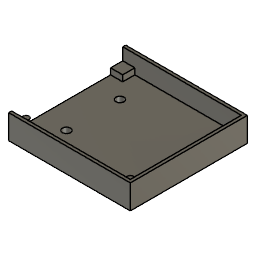
Controller Mounting (Autodesk Fusion 360 design; units mm, degrees)
Autodesk Fusion 360 part; units mm, degrees
sketch "Sketch1" plane through (0, 0, 0) normal (0, 0, 1) x (1, 0, 0)
  line L0 (0, 0) -> (65.175, 0)
  line L1 (65.175, 0) -> (65.175, 61.175)
  line L2 (65.175, 61.175) -> (0, 61.175)
  line L3 (0, 61.175) -> (0, 0)
  dimension "d1" = 61.175
  dimension "d2" = 65.175
  constraint horizontal L0
  constraint vertical L1
  constraint horizontal L2
  constraint vertical L3
  constraint coincident L0.start L3.end
  measures "d1" distance of L0.start L2.end
  measures "d2" distance of L0.start L0.end
extrude "Extrude1" add sketch "Sketch1" along normal blind 12.7
sketch "Sketch4" plane through (0, 0, 12.7) normal (0, 0, 1) x (-1, 0, 0)
  line L0 (0, -61.175) -> (0, 0)
  line L1 (0, 0) -> (-65.175, 0)
  line L2 (-65.175, 0) -> (-65.175, -61.175)
  line L3 (-65.175, -61.175) -> (0, -61.175)
  line L4 (-1.5875, -1.5875) -> (-63.5875, -1.5875)
  line L5 (-63.5875, -1.5875) -> (-63.5875, -59.5875)
  line L6 (-63.5875, -59.5875) -> (-1.5875, -59.5875)
  line L7 (-1.5875, -59.5875) -> (-1.5875, -1.5875)
  dimension "d10" = 1.5875
  dimension "d11" = 1.5875
  dimension "d12" = 1.5875
  dimension "d13" = 1.5875
  constraint horizontal L4
  constraint vertical L5
  constraint horizontal L6
  constraint vertical L7
  measures "d10" distance of L0 L7
  measures "d11" distance of L3 L6
  measures "d12" distance of L1 L4
  measures "d13" distance of L2 L5
extrude "Extrude2" cut sketch "Sketch4" against normal blind 9.525 contours L4 L5 L6 L7
sketch "Sketch5" plane through (0, 0, 0) normal (-1, 0, 0) x (0, -1, 0)
  line L0 (-61.175, 0) -> (0, 0)
  line L1 (0, 0) -> (0, 12.7)
  line L2 (0, 12.7) -> (-61.175, 12.7)
  line L3 (-61.175, 12.7) -> (-61.175, 0)
  line L4 (-53.2375, 12.7) -> (-7.9375, 12.7)
  line L5 (-7.9375, 12.7) -> (-7.9375, 0)
  line L6 (-53.2375, 0) -> (-53.2375, 12.7)
  line L7 (-53.2375, 3.175) -> (-59.5875, 3.175)
  line L8 (-59.5875, 3.175) -> (-59.5875, 12.7)
  line L9 (-59.5875, 12.7) -> (-53.2375, 12.7)
  line L10 (-53.2375, 12.7) -> (-53.2375, 3.175)
  line L11 (-7.9375, 3.175) -> (-1.5875, 3.175)
  line L12 (-1.5875, 3.175) -> (-1.5875, 12.7)
  line L13 (-1.5875, 12.7) -> (-7.9375, 12.7)
  line L14 (-7.9375, 12.7) -> (-7.9375, 3.175)
  line L15 (-53.2375, 3.175) -> (-7.9375, 3.175)
  dimension "d76" = 1.5875
  dimension "d77" = 3.175
  dimension "d78" = 3.175
  dimension "d79" = 1.5875
  dimension "d80" = 6.35
  dimension "d81" = 6.35
  constraint horizontal L4
  constraint vertical L5
  constraint vertical L6
  constraint coincident L2 L4.start
  constraint horizontal L5.end L6.start
  constraint horizontal L0.end L6.start
  constraint horizontal L7
  constraint vertical L8
  constraint horizontal L9
  constraint vertical L10
  constraint coincident L2 L8.end
  constraint coincident L6 L7.start
  constraint horizontal L11
  constraint vertical L12
  constraint horizontal L13
  constraint vertical L14
  constraint coincident L2 L12.end
  constraint coincident L5 L11.start
  measures "d76" distance of L3 L8
  measures "d77" distance of L0 L7
  measures "d78" distance of L0 L11
  measures "d79" distance of L1 L12
  measures "d80" distance of L8 L10
  measures "d81" distance of L12 L14
extrude "Extrude3" cut sketch "Sketch5" against normal blind 1.5875
sketch "Sketch6" plane through (0, 0, 3.175) normal (0, 0, 1) x (-1, 0, 0)
  circle A0 centre (-59.8375, -5.3375) radius 1.65
  circle A1 centre (-5.3375, -5.3375) radius 1.65
  circle A2 centre (-59.8375, -55.8375) radius 1.65
  circle A3 centre (-5.3375, -55.8375) radius 1.65
  line L0 (-63.5875, -1.5875) -> (-57.2375, -1.5875)
  line L1 (-57.2375, -1.5875) -> (-57.2375, -7.9375)
  line L2 (-57.2375, -7.9375) -> (-63.5875, -7.9375)
  line L3 (-63.5875, -7.9375) -> (-63.5875, -1.5875)
  line L4 (-63.5875, -59.5875) -> (-57.2375, -59.5875)
  line L5 (-57.2375, -59.5875) -> (-57.2375, -53.2375)
  line L6 (-57.2375, -53.2375) -> (-63.5875, -53.2375)
  line L7 (-63.5875, -53.2375) -> (-63.5875, -59.5875)
  line L8 (-1.5875, -59.5875) -> (-7.9375, -59.5875)
  line L9 (-7.9375, -59.5875) -> (-7.9375, -53.2375)
  line L10 (-7.9375, -53.2375) -> (-1.5875, -53.2375)
  line L11 (-1.5875, -53.2375) -> (-1.5875, -59.5875)
  line L12 (-1.5875, -1.5875) -> (-7.9375, -1.5875)
  line L13 (-7.9375, -1.5875) -> (-7.9375, -7.9375)
  line L14 (-7.9375, -7.9375) -> (-1.5875, -7.9375)
  line L15 (-1.5875, -7.9375) -> (-1.5875, -1.5875)
  line L16 (-65.175, 0) -> (-65.175, -61.175)
  line L17 (-65.175, -61.175) -> (0, -61.175)
  line L18 (-1.5875, -1.5875) -> (-63.5875, -1.5875)
  line L19 (-63.5875, -1.5875) -> (-63.5875, -59.5875)
  line L20 (-63.5875, -59.5875) -> (-1.5875, -59.5875)
  line L21 (-1.5875, -59.5875) -> (-1.5875, -1.5875)
  dimension "d82" = 3.3
  dimension "d83" = 50.5
  dimension "d84" = 50.5
  dimension "d85" = 54.5
  dimension "d86" = 3.3
  dimension "d87" = 3.3
  dimension "d88" = 5.3375
  dimension "d89" = 5.3375
  dimension "d90" = 6.35
  dimension "d91" = 6.35
  dimension "d92" = 6.35
  dimension "d93" = 6.35
  dimension "d94" = 6.35
  dimension "d95" = 6.35
  dimension "d96" = 6.35
  dimension "d97" = 6.35
  dimension "d98" = 1.5875
  dimension "d100" = 1.5875
  dimension "d101" = 1.5875
  dimension "d102" = 1.5875
  constraint horizontal A0.centre A1.centre
  constraint horizontal A2.centre A3.centre
  constraint vertical A1.centre A3.centre
  constraint equal A0 A1
  constraint horizontal L0
  constraint vertical L1
  constraint horizontal L2
  constraint vertical L3
  constraint horizontal L4
  constraint vertical L5
  constraint horizontal L6
  constraint vertical L7
  constraint horizontal L8
  constraint vertical L9
  constraint horizontal L10
  constraint vertical L11
  constraint horizontal L12
  constraint vertical L13
  constraint horizontal L14
  constraint vertical L15
  constraint horizontal L1.end L13.end
  constraint vertical L9.end L13.end
  constraint horizontal L5.end L9.end
  constraint vertical L1.end L5.end
  measures "d82" diameter of A0
  measures "d83" distance of A0.centre A2.centre
  measures "d84" vertical distance of A1.centre A3.centre
  measures "d85" distance of A0.centre A1.centre
  measures "d86" diameter of A2
  measures "d87" diameter of A3
  measures "d88" vertical distance of origin A0.centre
  measures "d89" horizontal distance of origin A1.centre
  measures "d90" distance of L12.end L13.end
  measures "d91" distance of L13.end L14.end
  measures "d92" distance of L9.end L10.end
  measures "d93" distance of L8.end L9.end
  measures "d94" distance of L4.end L5.end
  measures "d95" distance of L5.end L6.end
  measures "d96" distance of L1.end L2.end
  measures "d97" distance of L0.end L1.end
  measures "d98" distance of origin L12
  measures "d100" distance of origin L15
  measures "d101" distance of L3 L16
  measures "d102" distance of L4 L17
extrude "Extrude4" add sketch "Sketch6" along normal blind 3.175 contours A0 | A1 | A2 | A3 | L0 L1 L2 L3 L18 L19 | L12 L13 L14 L15 L18 L21 | L4 L5 L6 L7 L19 L20 | L8 L9 L10 L11 L20 L21
extrude "Extrude8" add sketch "Sketch6" along normal blind 6.35 contours A0 | A1
sketch "Sketch7" plane through (0, 0, 3.175) normal (0, 0, 1) x (-1, 0, 0)
  line L0 (-7.9375, -1.5875) -> (-57.2375, -1.5875)
  circle A0 centre (-15.2005, -16.6175) radius 2.1
  circle A1 centre (-15.2005, -44.5575) radius 2.1
  line L1 (-1.5875, 0) -> (-65.175, 0)
  line L2 (-15.2005, -16.6175) -> (-15.2005, -44.5575)
  line L3 (-15.2005, 0) -> (-15.2005, -61.175)
  line L4 (-65.175, -61.175) -> (-1.5875, -61.175)
  line L5 (-57.2375, -59.5875) -> (-7.9375, -59.5875)
  line L6 (-63.5875, -7.9375) -> (-63.5875, -53.2375)
  line L7 (-63.5875, -53.2375) -> (-57.2375, -53.2375)
  line L8 (-57.2375, -53.2375) -> (-57.2375, -59.5875)
  line L9 (-7.9375, -59.5875) -> (-7.9375, -53.2375)
  line L10 (-7.9375, -53.2375) -> (-1.5875, -53.2375)
  line L11 (-1.5875, -53.2375) -> (-1.5875, -7.9375)
  line L12 (-1.5875, -7.9375) -> (-7.9375, -7.9375)
  line L13 (-7.9375, -7.9375) -> (-7.9375, -1.5875)
  line L14 (-57.2375, -1.5875) -> (-57.2375, -7.9375)
  line L15 (-57.2375, -7.9375) -> (-63.5875, -7.9375)
  dimension "d41" = 4.2
  dimension "d42" = 4.2
  dimension "d43" = 27.94
  dimension "d108" = 13.613
  constraint vertical A0.centre A1.centre
  constraint coincident A0.centre L2.start
  constraint coincident A1.centre L2.end
  constraint coincident L1 L3.start
  constraint midpoint L2 L3
  constraint coincident L3.end L4
  constraint vertical L3.start L3.end
  measures "d41" diameter of A1
  measures "d42" diameter of A0
  measures "d43" distance of A0.centre A1.centre
  measures "d108" distance of L2 L11
extrude "Extrude5" cut sketch "Sketch7" against normal blind 3.175 contours A0 L2 L3 | A0 L2 L3 | A1 L2 L3 | A1 L2 L3
sketch "Sketch9" plane through (0, 0, 0) normal (0, 0, -1) x (1, 0, 0)
  line L0 (1.5875, -61.175) -> (65.175, -61.175)
  line L1 (65.175, -61.175) -> (65.175, 0)
  line L2 (65.175, 0) -> (1.5875, 0)
  circle A0 centre (19.0373, -54.4) radius 1.6
  circle A1 centre (44.4373, -54.4) radius 1.6
  circle A2 centre (19.0373, -6.775) radius 1.6
  circle A3 centre (44.4373, -6.775) radius 1.6
  circle A4 centre (15.2005, -16.6175) radius 2.1
  circle A5 centre (15.2005, -44.5575) radius 2.1
  line L3 (44.4373, -6.775) -> (44.4373, 0)
  line L4 (44.4373, -54.4) -> (44.4373, -61.175)
  line L5 (1.5875, 0) -> (1.5875, -61.175)
  dimension "d60" = 3.2
  dimension "d61" = 3.2
  dimension "d75" = 25.4
  dimension "d105" = 47.625
  dimension "d106" = 47.625
  constraint vertical A0.centre A2.centre
  constraint vertical A1.centre A3.centre
  constraint equal A0 A2
  constraint equal A0 A3
  constraint horizontal A2.centre A3.centre
  constraint coincident A3.centre L3.start
  constraint coincident L2 L3.end
  constraint perpendicular L2 L3
  constraint coincident A1.centre L4.start
  constraint coincident L0 L4.end
  constraint perpendicular L0 L4
  constraint equal L3 L4
  measures "d60" diameter of A0
  measures "d61" diameter of A1
  measures "d75" distance of A0.centre A1.centre
  measures "d105" distance of A1.centre A3.centre
  measures "d106" distance of A0.centre A2.centre
equation "d1 = 58 mm + 0.125 in"
equation "d2 = 62 mm + 0.125 in"
equation "d10 = ( 1 / 16 ) * 1 in"
equation "d11 = ( 1 / 16 ) * 1 in"
equation "d12 = ( 1 / 16 ) * 1 in"
equation "d13 = ( 1 / 16 ) * 1 in"
equation "d14 = -0.5 in + 0.125 in"
equation "d20 = ( -1 / 16 ) * 1 in"
equation "d76 = ( 1 / 16 ) * 1 in"
equation "d79 = ( 1 / 16 ) * 1 in"
equation "d88 = ( 1 / 16 ) * 1 in + 3.75 mm"
equation "d89 = ( 1 / 16 ) * 1 in + 3.75 mm"
equation "d98 = ( 1 / 16 ) * 1 in"
equation "d100 = ( 1 / 16 ) * 1 in"
equation "d101 = ( 1 / 16 ) * 1 in"
equation "d102 = ( 1 / 16 ) * 1 in"
